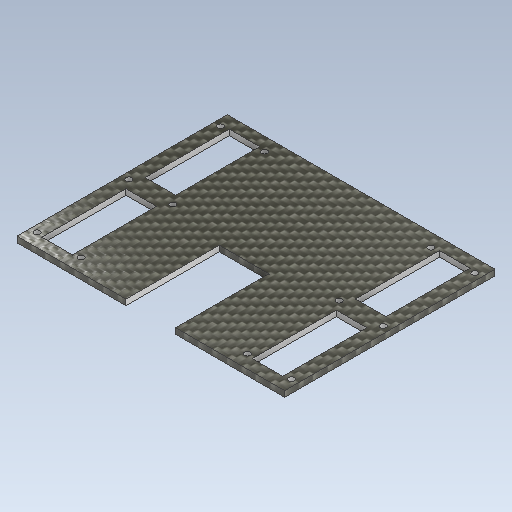
# Autodesk Inventor part: Bodenplatte
Saved by Autodesk Inventor 2026.4 (Build 304435030, 435C)
## iProperties
Created: 2026-11-14
Part Number: Bodenplatte
Material: Generisch
Document SubType Name: Modeling
Designer: weira
Density: 1 g/cm^3
Appearance: Vorgabe
Author: weira
Autodesk Inventor part; units mm, degrees
ref_plane "YZ Plane" through (0, 0, 0) normal (1, 0, 0) x (0, 1, 0)
ref_plane "XZ Plane" through (0, 0, 0) normal (0, 1, 0) x (-1, 0, 0)
ref_plane "XY Plane" through (0, 0, 0) normal (0, 0, 1) x (1, 0, 0)
sketch "Skizze1" plane through (0, 0, 0) normal (0, 0, 1) x (1, 0, 0)
  line L0 (77.0318, 61.1859) -> (77.0318, -48.8141)
  line L1 (-62.9682, -48.8141) -> (-62.9682, 61.1859)
  line L2 (-55.9682, -48.8141) -> (-62.9682, -48.8141)
  line L3 (70.0318, -48.8141) -> (77.0318, -48.8141)
  line L4 (70.0318, 61.1859) -> (77.0318, 61.1859)
  line L5 (-55.9682, 61.1859) -> (-62.9682, 61.1859)
  line L6 (-39.9682, 61.1859) -> (-32.9682, 61.1859)
  line L7 (-32.9682, 61.1859) -> (-32.9682, -48.8141)
  line L8 (54.0318, 61.1859) -> (47.0318, 61.1859)
  line L9 (47.0318, -48.8141) -> (47.0318, 61.1859)
  line L10 (-32.9682, 0) -> (47.0318, 0)
  line L11 (-62.9682, 61.1859) -> (77.0318, 61.1859)
  line L12 (77.0318, 61.1859) -> (77.0318, 66.1859)
  line L13 (77.0318, 66.1859) -> (-62.9682, 66.1859)
  line L14 (-62.9682, 66.1859) -> (-62.9682, 61.1859)
  line L15 (-62.9682, -48.8141) -> (-32.9682, -48.8141)
  line L16 (77.0318, -48.8141) -> (46.5489, -48.8141)
  point P0 (0, 0)
  dimension "d0" = 5
  dimension "d1" = 90
  dimension "d2" = 90
  dimension "d3" = 90
  dimension "d4" = 90
  dimension "d5" = 90
  dimension "d6" = 90
  dimension "d7" = 30
  dimension "d8" = 110
  dimension "d9" = 140
  dimension "d10" = 5
  dimension "d11" = 61.1859
  dimension "d12" = 110
  dimension "d13" = 77.0318
  dimension "d14" = 77.0318
  dimension "d15" = 61.1859
  dimension "d16" = 48.8141
  dimension "d17" = 61.1859
  dimension "d18" = 61.1859
  dimension "d19" = 7
  dimension "d20" = 7
  dimension "d21" = 23
  dimension "d22" = 110
  dimension "d23" = 110
  dimension "d24" = 117
  dimension "d25" = 133
  dimension "d26" = 133
  constraints: 34 end point, 6 parallel, 3 point on line, 2 perpendicular, 1 horizontal
  measures "d0" distance between parallel lines of L11 L13
  measures "d1" angle of L4 L12
  measures "d2" angle of L3 L12
  measures "d3" angle of L6 L12
  measures "d4" angle of L5 L12
  measures "d5" angle of L4 L0
  measures "d6" angle of L4 L1
  measures "d7" distance between parallel lines of L9 L12
  measures "d8" distance between parallel lines of L7 L12
  measures "d9" distance between parallel lines of L12 L14
  measures "d10" distance between parallel lines of L8 L13
  measures "d11" distance between parallel lines of L8 L10
  measures "d12" distance between parallel lines of L8 L2
  measures "d13" distance from line of point (0, 0) L12
  measures "d14" distance from line of point (0, 0) L0
  measures "d15" distance from line of point (0, 0) L4
  measures "d16" distance from line of point (0, 0) L3
  measures "d17" distance from line of point (0, 0) L8
  measures "d18" distance from line of point (0, 0) L6
  measures "d19" distance from line of L4.start L12
  measures "d20" distance from line of L3.start L12
  measures "d21" distance from line of L8.start L12
  measures "d22" distance from line of L9.start L4
  measures "d23" distance from line of L7.end L4
  measures "d24" distance from line of L6.start L12
  measures "d25" distance from line of L5.start L12
  measures "d26" distance from line of L2.start L12
extrude "Extrusion1" add sketch "Skizze1" along normal blind 3
sketch "Skizze2" plane through (0, 0, 3) normal (0, 0, 1) x (1, 0, 0)
  circle A0 centre (267.7608, 2.9509) radius 2.5
  circle A1 centre (244.7608, 2.9509) radius 2.5
  line L0 (271.2608, 105.9509) -> (271.2608, -4.0491)
  line L1 (264.2608, -4.0491) -> (271.2608, -4.0491)
  line L2 (264.2608, -4.0491) -> (264.2608, 105.9509)
  circle A2 centre (267.7608, 98.9509) radius 2.5
  circle A3 centre (244.7608, 98.9509) radius 2.2295
  circle A4 centre (244.7608, 98.9509) radius 2.5
  circle A5 centre (244.7608, 50.9509) radius 2.5
  circle A6 centre (267.7608, 50.9509) radius 2.5
  circle A7 centre (157.7608, 2.9509) radius 2.5
  circle A8 centre (157.7608, 50.9509) radius 2.5
  circle A9 centre (134.7608, 2.9509) radius 2.5
  circle A10 centre (134.7608, 50.9509) radius 2.5
  circle A11 centre (134.7608, 98.9509) radius 2.5
  circle A12 centre (157.7608, 98.9509) radius 2.5
  line L3 (131.2608, -4.0491) -> (131.2608, 105.9509)
  line L4 (138.2608, -4.0491) -> (131.2608, -4.0491)
  line L5 (47.0318, 0) -> (47.0318, -48.8141) projected
  line L6 (47.0318, -48.8141) -> (77.0318, -48.8141) projected
  line L7 (77.0318, -48.8141) -> (77.0318, 66.1859) projected
  line L8 (77.0318, 66.1859) -> (-62.9682, 66.1859) projected
  line L9 (-62.9682, 66.1859) -> (-62.9682, -48.8141) projected
  line L10 (-62.9682, -48.8141) -> (-32.9682, -48.8141) projected
  line L11 (-32.9682, -48.8141) -> (-32.9682, 0) projected
  line L12 (-32.9682, 0) -> (47.0318, 0) projected
  circle A13 centre (73.5318, -41.8141) radius 2.5
  circle A14 centre (50.5318, -41.8141) radius 2.5
  line L13 (77.0318, 61.1859) -> (77.0318, -48.8141)
  line L14 (70.0318, -48.8141) -> (77.0318, -48.8141)
  line L15 (70.0318, -48.8141) -> (70.0318, 61.1859)
  circle A15 centre (73.5318, 54.1859) radius 2.5
  circle A16 centre (50.5318, 54.1859) radius 2.2295
  circle A17 centre (50.5318, 54.1859) radius 2.5
  circle A18 centre (50.5318, 6.1859) radius 2.5
  circle A19 centre (73.5318, 6.1859) radius 2.5
  circle A20 centre (-36.4682, -41.8141) radius 2.5
  circle A21 centre (-36.4682, 6.1859) radius 2.5
  circle A22 centre (-59.4682, -41.8141) radius 2.5
  circle A23 centre (-59.4682, 6.1859) radius 2.5
  circle A24 centre (-59.4682, 54.1859) radius 2.5
  circle A25 centre (-36.4682, 54.1859) radius 2.5
  line L16 (-62.9682, -48.8141) -> (-62.9682, 61.1859)
  line L17 (-55.9682, -48.8141) -> (-62.9682, -48.8141)
  line L18 (47.0318, 0) -> (47.0318, -48.8141) projected
  point P0 (0, 0)
  dimension "d29" = 26.5
  constraints: 26 centre point, 20 end point
  measures "d29" distance from line of L18 A13.centre
hole "Bohrung1" at (-59.4682, -41.8141, 3) at (-36.4682, -41.8141, 3) at (-36.4682, 6.1859, 3) at (-59.4682, 6.1859, 3) at (-59.4682, 54.1859, 3) at (-36.4682, 54.1859, 3) at (50.5318, 54.1859, 3) at (73.5318, 54.1859, 3) at (73.5318, 6.1859, 3) at (73.5318, -41.8141, 3) at (50.5318, -41.8141, 3) at (50.5318, 6.1859, 3) direction (0, 0, -1) diameter 3 end through all
sketch "Skizze3" plane through (0, 0, 3) normal (0, 0, 1) x (1, 0, 0)
  circle A0 centre (50.5318, 6.1859) radius 1.5 projected
  circle A1 centre (50.5318, -41.8141) radius 1.5 projected
  circle A2 centre (73.5318, -41.8141) radius 1.5 projected
  circle A3 centre (73.5318, 6.1859) radius 1.5 projected
  circle A4 centre (73.5318, 54.1859) radius 1.5 projected
  circle A5 centre (50.5318, 54.1859) radius 1.5 projected
  circle A6 centre (-36.4682, 54.1859) radius 1.5 projected
  circle A7 centre (-59.4682, 54.1859) radius 1.5 projected
  circle A8 centre (-59.4682, 6.1859) radius 1.5 projected
  circle A9 centre (-36.4682, 6.1859) radius 1.5 projected
  circle A10 centre (-36.4682, -41.8141) radius 1.5 projected
  circle A11 centre (-59.4682, -41.8141) radius 1.5 projected
  line L0 (47.0318, 0) -> (47.0318, -48.8141) projected
  line L1 (47.0318, -48.8141) -> (77.0318, -48.8141) projected
  line L2 (77.0318, -48.8141) -> (77.0318, 66.1859) projected
  line L3 (77.0318, 66.1859) -> (-62.9682, 66.1859) projected
  line L4 (-62.9682, 66.1859) -> (-62.9682, -48.8141) projected
  line L5 (-62.9682, -48.8141) -> (-32.9682, -48.8141) projected
  line L6 (-32.9682, -48.8141) -> (-32.9682, 0) projected
  line L7 (-32.9682, 0) -> (47.0318, 0) projected
  line L8 (77.0318, 66.1859) -> (-62.9682, 66.1859) projected
  line L9 (-62.9682, 66.1859) -> (77.0318, 66.1859)
  line L10 (77.0318, 66.1859) -> (77.0318, 61.1859)
  line L11 (77.0318, 61.1859) -> (-62.9682, 61.1859)
  line L12 (-62.9682, 61.1859) -> (-62.9682, 66.1859)
  line L13 (-59.4682, 6.1859) -> (-36.4682, -41.8141) construction
  line L14 (-36.4682, 6.1859) -> (-59.4682, -41.8141) construction
  line L15 (-59.4682, 6.1859) -> (-36.4682, 54.1859) construction
  circle A12 centre (-59.4682, 54.1859) radius 1.5 projected
  line L16 (-59.4682, 54.1859) -> (-36.4682, 6.1859) construction
  line L17 (-55.9682, 49.1859) -> (-39.9682, 49.1859)
  line L18 (-39.9682, 49.1859) -> (-39.9682, 11.1859)
  line L19 (-39.9682, 11.1859) -> (-55.9682, 11.1859)
  line L20 (-55.9682, 11.1859) -> (-55.9682, 49.1859)
  line L21 (-55.9682, 49.1859) -> (-39.9682, 11.1859) construction
  line L22 (-39.9682, 49.1859) -> (-55.9682, 11.1859) construction
  line L23 (-55.9682, 1.1859) -> (-39.9682, 1.1859)
  line L24 (-39.9682, 1.1859) -> (-39.9682, -36.8141)
  line L25 (-39.9682, -36.8141) -> (-55.9682, -36.8141)
  line L26 (-55.9682, -36.8141) -> (-55.9682, 1.1859)
  line L27 (-55.9682, 1.1859) -> (-39.9682, -36.8141) construction
  line L28 (-39.9682, 1.1859) -> (-55.9682, -36.8141) construction
  line L29 (7.0318, 85.5354) -> (7.0318, -61.336) construction
  circle A13 centre (50.5318, 54.1859) radius 1.5
  circle A14 centre (73.5318, 54.1859) radius 1.5
  circle A15 centre (73.5318, 6.1859) radius 1.5
  circle A16 centre (50.5318, 6.1859) radius 1.5
  circle A17 centre (50.5318, -41.8141) radius 1.5
  circle A18 centre (73.5318, -41.8141) radius 1.5
  line L30 (77.0318, -48.8141) -> (47.0318, -48.8141)
  line L31 (47.0318, -48.8141) -> (47.0318, 0)
  line L32 (73.5318, 6.1859) -> (50.5318, -41.8141) construction
  line L33 (50.5318, 6.1859) -> (73.5318, -41.8141) construction
  line L34 (73.5318, 6.1859) -> (50.5318, 54.1859) construction
  circle A19 centre (73.5318, 54.1859) radius 1.5
  line L35 (73.5318, 54.1859) -> (50.5318, 6.1859) construction
  line L36 (70.0318, 49.1859) -> (54.0318, 49.1859)
  line L37 (54.0318, 49.1859) -> (54.0318, 11.1859)
  line L38 (54.0318, 11.1859) -> (70.0318, 11.1859)
  line L39 (70.0318, 11.1859) -> (70.0318, 49.1859)
  line L40 (70.0318, 49.1859) -> (54.0318, 11.1859) construction
  line L41 (54.0318, 49.1859) -> (70.0318, 11.1859) construction
  line L42 (70.0318, 1.1859) -> (54.0318, 1.1859)
  line L43 (54.0318, 1.1859) -> (54.0318, -36.8141)
  line L44 (54.0318, -36.8141) -> (70.0318, -36.8141)
  line L45 (70.0318, -36.8141) -> (70.0318, 1.1859)
  line L46 (70.0318, 1.1859) -> (54.0318, -36.8141) construction
  line L47 (54.0318, 1.1859) -> (70.0318, -36.8141) construction
  line L48 (-55.9682, 49.1859) -> (-39.9682, 49.1859)
  line L49 (-39.9682, 49.1859) -> (-39.9682, 55.1859)
  line L50 (-39.9682, 55.1859) -> (-55.9682, 55.1859)
  line L51 (-55.9682, 55.1859) -> (-55.9682, 49.1859)
  line L52 (-55.9682, -36.8141) -> (-39.9682, -36.8141)
  line L53 (-39.9682, -36.8141) -> (-39.9682, -42.8141)
  line L54 (-39.9682, -42.8141) -> (-55.9682, -42.8141)
  line L55 (-55.9682, -42.8141) -> (-55.9682, -36.8141)
  line L56 (54.0318, 49.1859) -> (70.0318, 49.1859)
  line L57 (70.0318, 49.1859) -> (70.0318, 55.1859)
  line L58 (70.0318, 55.1859) -> (54.0318, 55.1859)
  line L59 (54.0318, 55.1859) -> (54.0318, 49.1859)
  line L60 (54.0318, -36.8141) -> (70.0318, -36.8141)
  line L61 (70.0318, -36.8141) -> (70.0318, -42.8141)
  line L62 (70.0318, -42.8141) -> (54.0318, -42.8141)
  line L63 (54.0318, -42.8141) -> (54.0318, -36.8141)
  point P0 (0, 0)
  point P1 (7.0318, 61.1859)
  point P2 (-47.9682, -17.8141)
  point P3 (-47.9682, 30.1859)
  point P4 (62.0318, -17.8141)
  point P5 (62.0318, 30.1859)
  point P6 (-47.9682, -36.8141)
  point P7 (62.0318, 55.1859)
  point P8 (62.0318, -42.8141)
  dimension "d37" = 5
  dimension "d38" = 3.5
  dimension "d39" = 5
  dimension "d40" = 3.5
  dimension "d41" = 5
  dimension "d42" = 140
  dimension "d43" = 70
  dimension "d46" = 6
  dimension "d47" = 6
  dimension "d48" = 6
  dimension "d49" = 6
  constraints: 110 end point, 17 symmetric about line, 14 parallel, 13 midpoint, 7 centre point, 7 horizontal, 7 perpendicular, 1 point on line, 1 vertical, 7 other
  measures "d37" distance from line of L3 point (7.032, 61.186)
  measures "d38" distance from line of L26 L13.start
  measures "d39" distance from line of L23 L13.start
  measures "d40" distance from line of A7.centre L20
  measures "d41" distance from line of L19 L13.start
  measures "d42" distance between parallel lines of L2 L4
  measures "d43" distance between parallel lines of L4 L29
  measures "d46" distance between parallel lines of L17 L50
  measures "d47" distance from line of point (-47.968, -36.814) L54
  measures "d48" distance from line of L36 point (62.032, 55.186)
  measures "d49" distance from line of point (62.032, -42.814) L44
extrude "Extrusion2" cut sketch "Skizze3" against normal blind 10 contours L51 L50 L49 L17 | L17 L18 L19 L20 | L23 L24 L25 L26 | L25 L53 L54 L55 | L39 L38 L37 L36 | L36 L59 L58 L57 | L45 L44 L43 L42 | L61 L62 L63 L44
sketch "Skizze4" plane through (0, 0, 3) normal (0, 0, 1) x (1, 0, 0)
  line L0 (70.0318, -42.8141) -> (54.0318, -42.8141) projected
  line L1 (54.0318, -42.8141) -> (54.0318, 1.1859) projected
  line L2 (54.0318, 1.1859) -> (70.0318, 1.1859) projected
  line L3 (70.0318, 1.1859) -> (70.0318, -42.8141) projected
  line L4 (-55.9682, 1.1859) -> (-39.9682, 1.1859) projected
  line L5 (-39.9682, 1.1859) -> (-39.9682, -42.8141) projected
  line L6 (-39.9682, -42.8141) -> (-55.9682, -42.8141) projected
  line L7 (-55.9682, -42.8141) -> (-55.9682, 1.1859) projected
  line L8 (70.0318, 55.1859) -> (70.0318, 11.1859) projected
  line L9 (70.0318, 11.1859) -> (54.0318, 11.1859) projected
  line L10 (54.0318, 11.1859) -> (54.0318, 55.1859) projected
  line L11 (54.0318, 55.1859) -> (70.0318, 55.1859) projected
  line L12 (-39.9682, 55.1859) -> (-39.9682, 11.1859) projected
  line L13 (-39.9682, 11.1859) -> (-55.9682, 11.1859) projected
  line L14 (-55.9682, 11.1859) -> (-55.9682, 55.1859) projected
  line L15 (-55.9682, 55.1859) -> (-39.9682, 55.1859) projected
  circle A0 centre (50.5318, 6.1859) radius 1.5 projected
  circle A1 centre (50.5318, -41.8141) radius 1.5 projected
  circle A2 centre (73.5318, -41.8141) radius 1.5 projected
  circle A3 centre (73.5318, 6.1859) radius 1.5 projected
  circle A4 centre (73.5318, 54.1859) radius 1.5 projected
  circle A5 centre (50.5318, 54.1859) radius 1.5 projected
  circle A6 centre (-36.4682, 54.1859) radius 1.5 projected
  circle A7 centre (-59.4682, 54.1859) radius 1.5 projected
  circle A8 centre (-59.4682, 6.1859) radius 1.5 projected
  circle A9 centre (-36.4682, 6.1859) radius 1.5 projected
  circle A10 centre (-36.4682, -41.8141) radius 1.5 projected
  circle A11 centre (-59.4682, -41.8141) radius 1.5 projected
  line L16 (47.0318, 0) -> (47.0318, -48.8141) projected
  line L17 (47.0318, -48.8141) -> (77.0318, -48.8141) projected
  line L18 (77.0318, -48.8141) -> (77.0318, 66.1859) projected
  line L19 (77.0318, 66.1859) -> (-62.9682, 66.1859) projected
  line L20 (-62.9682, 66.1859) -> (-62.9682, -48.8141) projected
  line L21 (-62.9682, -48.8141) -> (-32.9682, -48.8141) projected
  line L22 (-32.9682, -48.8141) -> (-32.9682, 0) projected
  line L23 (-32.9682, 0) -> (47.0318, 0) projected
  line L24 (-32.9682, -48.8141) -> (-5.9682, -48.8141)
  line L25 (-5.9682, -48.8141) -> (-5.9682, 0)
  line L26 (-5.9682, 0) -> (-32.9682, 0)
  line L27 (-32.9682, 0) -> (-32.9682, -48.8141)
  line L28 (47.0318, -48.8141) -> (20.0318, -48.8141)
  line L29 (20.0318, -48.8141) -> (20.0318, 0)
  line L30 (20.0318, 0) -> (47.0318, 0)
  line L31 (47.0318, 0) -> (47.0318, -48.8141)
  point P0 (0, 0)
  dimension "d50" = 27
  dimension "d51" = 27
  constraints: 16 end point, 4 parallel, 2 horizontal, 2 perpendicular, 2 point on line
  measures "d50" distance between parallel lines of L27 L25
  measures "d51" distance between parallel lines of L16 L29
extrude "Extrusion3" add sketch "Skizze4" against normal up to surface (3 mm away) contours L16 L28 L29 L23 | L25 L24 L22 L23
sketch "Skizze5" plane through (0, 0, 3) normal (0, 0, 1) x (1, 0, 0)
  line L0 (70.0318, -42.8141) -> (54.0318, -42.8141) projected
  line L1 (54.0318, -42.8141) -> (54.0318, 1.1859) projected
  line L2 (54.0318, 1.1859) -> (70.0318, 1.1859) projected
  line L3 (70.0318, 1.1859) -> (70.0318, -42.8141) projected
  line L4 (-55.9682, 1.1859) -> (-39.9682, 1.1859) projected
  line L5 (-39.9682, 1.1859) -> (-39.9682, -42.8141) projected
  line L6 (-39.9682, -42.8141) -> (-55.9682, -42.8141) projected
  line L7 (-55.9682, -42.8141) -> (-55.9682, 1.1859) projected
  line L8 (70.0318, 55.1859) -> (70.0318, 11.1859) projected
  line L9 (70.0318, 11.1859) -> (54.0318, 11.1859) projected
  line L10 (54.0318, 11.1859) -> (54.0318, 55.1859) projected
  line L11 (54.0318, 55.1859) -> (70.0318, 55.1859) projected
  line L12 (-39.9682, 55.1859) -> (-39.9682, 11.1859) projected
  line L13 (-39.9682, 11.1859) -> (-55.9682, 11.1859) projected
  line L14 (-55.9682, 11.1859) -> (-55.9682, 55.1859) projected
  line L15 (-55.9682, 55.1859) -> (-39.9682, 55.1859) projected
  circle A0 centre (50.5318, 6.1859) radius 1.5 projected
  circle A1 centre (50.5318, -41.8141) radius 1.5 projected
  circle A2 centre (73.5318, -41.8141) radius 1.5 projected
  circle A3 centre (73.5318, 6.1859) radius 1.5 projected
  circle A4 centre (73.5318, 54.1859) radius 1.5 projected
  circle A5 centre (50.5318, 54.1859) radius 1.5 projected
  circle A6 centre (-36.4682, 54.1859) radius 1.5 projected
  circle A7 centre (-59.4682, 54.1859) radius 1.5 projected
  circle A8 centre (-59.4682, 6.1859) radius 1.5 projected
  circle A9 centre (-36.4682, 6.1859) radius 1.5 projected
  circle A10 centre (-36.4682, -41.8141) radius 1.5 projected
  circle A11 centre (-59.4682, -41.8141) radius 1.5 projected
  line L16 (20.0318, -48.8141) -> (77.0318, -48.8141) projected
  line L17 (77.0318, -48.8141) -> (77.0318, 66.1859) projected
  line L18 (77.0318, 66.1859) -> (-62.9682, 66.1859) projected
  line L19 (-62.9682, 66.1859) -> (-62.9682, -48.8141) projected
  line L20 (-62.9682, -48.8141) -> (-5.9682, -48.8141) projected
  line L21 (-5.9682, -48.8141) -> (-5.9682, 0) projected
  line L22 (-5.9682, 0) -> (20.0318, 0) projected
  line L23 (20.0318, 0) -> (20.0318, -48.8141) projected
  line L24 (-62.9682, 66.1859) -> (77.0318, 66.1859)
  line L25 (77.0318, 66.1859) -> (77.0318, 61.1859)
  line L26 (77.0318, 61.1859) -> (-62.9682, 61.1859)
  line L27 (-62.9682, 61.1859) -> (-62.9682, 66.1859)
  point P0 (0, 0)
  point P1 (-62.9682, 61.1859)
  dimension "d54" = 5
  constraints: 8 end point, 2 parallel, 1 horizontal, 1 perpendicular, 1 point on line
  measures "d54" distance between parallel lines of L24 L26
extrude "Extrusion4" cut sketch "Skizze5" against normal blind 10 contours L26 L19 L18 L17
equation "\"d38\" = d40"
equation "\"d39\" = d41"
equation "\"d43\" = 0.5 * d42"
equation "\"d48\" = d46"
equation "\"d49\" = d47"
equation "\"d51\" = d50"
